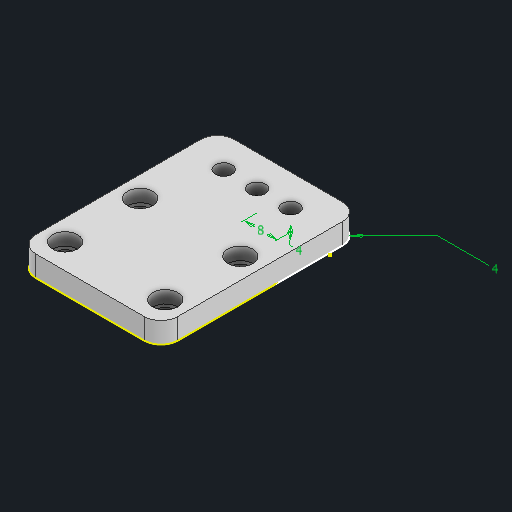
# Autodesk Inventor part: UR_rail_R_LinearWayCopler_v3
Saved by Autodesk Inventor 2026.2 (Build 302298000, 298)
## iProperties
Created: 2025-11-14
Part Number: UR_rail_R_LinearWayCopler_v3
Material: 일반
Document SubType Name: Modeling
Designer: work
Density: 1 g/cm^3
Appearance: 기본값
Author: work
Autodesk Inventor part; units mm, degrees
ref_plane "YZ Plane" through (0, 0, 0) normal (1, 0, 0) x (0, 1, 0)
ref_plane "XZ Plane" through (0, 0, 0) normal (0, 1, 0) x (-1, 0, 0)
ref_plane "XY Plane" through (0, 0, 0) normal (0, 0, 1) x (1, 0, 0)
sketch "스케치1" plane through (0, 0, 0) normal (0, 1, 0) x (-1, 0, 0)
  line L0 (-17, 15) -> (17, 15)
  line L1 (17, 15) -> (17, -15)
  line L2 (17, -15) -> (-17, -15)
  line L3 (-17, -15) -> (-17, 15)
  line L4 (-17, 15) -> (17, -15) construction
  line L5 (17, 15) -> (-17, -15) construction
  line L6 (12, 9) -> (-12, 9) construction
  line L7 (-12, 9) -> (-12, -9) construction
  line L8 (-12, -9) -> (12, -9) construction
  line L9 (12, -9) -> (12, 9) construction
  line L10 (12, 9) -> (-12, -9) construction
  line L11 (-12, 9) -> (12, -9) construction
  circle A0 centre (12, 9) radius 2
  circle A1 centre (12, -9) radius 2
  circle A2 centre (-12, 9) radius 2
  circle A3 centre (-12, -9) radius 2
  circle A4 centre (0, -25) radius 2
  circle A5 centre (0, -25) radius 7.5
  arc A6 (17, -15) -> (7.5, -25) centre (17.5132, -25) ccw
  arc A7 (-7.5, -25) -> (-17, -15) centre (-17.5132, -25) ccw
  line L12 (7.5, -25) -> (-7.5, -25) construction
  line L13 (0, -25) -> (0, 0) construction
  dimension "d0" = 34
  dimension "d1" = 30
  dimension "d2" = 24
  dimension "d3" = 18
  dimension "d4" = 4
  dimension "d5" = 4
  dimension "d6" = 4
  dimension "d7" = 4
  dimension "d8" = 4
  dimension "d9" = 15
  dimension "d10" = 25
  dimension "d11" = 15
  constraints: 28 end point, 8 centre point, 6 point on circle, 5 coincident, 4 midpoint, 4 parallel, 3 horizontal, 2 perpendicular, 2 tangent, 1 vertical
  measures "d0" distance of L1.end L2.end
  measures "d1" distance of L0.end L1.end
  measures "d2" distance of L8.end L7.end
  measures "d3" distance of L7.end L6.end
  measures "d4" diameter of A0
  measures "d5" diameter of A1
  measures "d6" diameter of A2
  measures "d7" diameter of A3
  measures "d8" diameter of A4
  measures "d9" diameter of A5
  measures "d10" distance of A4.centre L13.end
  measures "d11" distance of L12.start L12.end
extrude "돌출1" add sketch "스케치1" along normal blind 5
fillet "모깎기1" radius 4 4 edges at (-17, 2.5, 15) (17, 2.5, 15) (17, 2.5, -15) (-17, 2.5, -15)
sketch "스케치2" plane through (0, 5, 0) normal (0, 1, 0) x (1, 0, 0)
  arc A0 (-14.2883, 15.5204) -> (-17, 11.7335) centre (-13, 11.7335) ccw projected
  line L0 (-17, 11.7335) -> (-17, -11) projected
  arc A1 (-17, -11) -> (-13, -15) centre (-13, -11) ccw projected
  line L1 (-13, -15) -> (13, -15) projected
  arc A2 (13, -15) -> (17, -11) centre (13, -11) ccw projected
  line L2 (17, -11) -> (17, 11.7335) projected
  arc A3 (17, 11.7335) -> (14.2883, 15.5204) centre (13, 11.7335) ccw projected
  arc A4 (7.5, 25) -> (14.2883, 15.5204) centre (17.5132, 25) ccw projected
  arc A5 (7.5, 25) -> (-7.5, 25) centre (0, 25) ccw projected
  arc A6 (-14.2883, 15.5204) -> (-7.5, 25) centre (-17.5132, 25) ccw projected
  circle A7 centre (0, 25) radius 2 projected
  circle A8 centre (-12, -9) radius 2 projected
  circle A9 centre (-12, 9) radius 2 projected
  circle A10 centre (12, -9) radius 2 projected
  circle A11 centre (12, 9) radius 2 projected
  circle A12 centre (-12, -9) radius 3
  circle A13 centre (-12, 9) radius 3
  circle A14 centre (12, 9) radius 3
  circle A15 centre (12, -9) radius 3
  point P0 (0, 0)
  dimension "d15" = 6
  dimension "d16" = 6
  dimension "d17" = 6
  dimension "d18" = 6
  constraints: 4 centre point, 4 coincident
  measures "d15" diameter of A12
  measures "d16" diameter of A14
  measures "d17" diameter of A15
  measures "d18" diameter of A13
extrude "돌출2" cut sketch "스케치2" against normal blind 3 contours A8 | A9 | A10 | A11 | A12 | A13 | A14 | A15
sketch "스케치3" plane through (0, 0, 0) normal (0, -1, 0) x (1, 0, 0)
  circle A0 centre (12, 9) radius 3 projected
  circle A1 centre (-12, -9) radius 3 projected
  circle A2 centre (12, -9) radius 3 projected
  circle A3 centre (-12, 9) radius 3 projected
  arc A4 (-17, -11.7335) -> (-14.2883, -15.5204) centre (-13, -11.7335) ccw projected
  line L0 (-17, -11.7335) -> (-17, 11) projected
  arc A5 (-13, 15) -> (-17, 11) centre (-13, 11) ccw projected
  line L1 (-13, 15) -> (13, 15) projected
  arc A6 (17, 11) -> (13, 15) centre (13, 11) ccw projected
  line L2 (17, 11) -> (17, -11.7335) projected
  arc A7 (14.2883, -15.5204) -> (17, -11.7335) centre (13, -11.7335) ccw projected
  arc A8 (14.2883, -15.5204) -> (7.5, -25) centre (17.5132, -25) ccw projected
  arc A9 (-7.5, -25) -> (7.5, -25) centre (0, -25) ccw projected
  arc A10 (-7.5, -25) -> (-14.2883, -15.5204) centre (-17.5132, -25) ccw projected
  circle A11 centre (0, -25) radius 2 projected
  line L3 (0, -25) -> (8, -25) construction
  circle A12 centre (8, -25) radius 2
  line L4 (0, -32.5) -> (13, -32.5)
  arc A13 (-7.5, -25) -> (7.5, -25) centre (0, -25) ccw projected
  line L5 (17, -28.5) -> (17, -11.7335)
  arc A14 (13, -32.5) -> (17, -28.5) centre (13, -28.5) ccw
  line L6 (0, -32.5) -> (0, -25) construction
  circle A15 centre (-8, -25) radius 2
  line L7 (0, -32.5) -> (-13, -32.5)
  line L8 (-17, -28.5) -> (-17, -11.7335)
  arc A16 (-17, -28.5) -> (-13, -32.5) centre (-13, -28.5) ccw
  point P0 (0, 0)
  point P1 (-17.5132, -25)
  point P2 (7.6971, -23.0231)
  point P3 (7.2656, -26.8603)
  point P4 (-7.2656, -26.8603)
  point P5 (-7.6971, -23.0231)
  dimension "d21" = 8
  dimension "d22" = 4
  dimension "d23" = 4
  constraints: 12 end point, 5 point on circle, 5 symmetric about line, 4 centre point, 3 tangent, 2 horizontal, 1 coincident, 1 perpendicular, 1 vertical, 2 other
  measures "d21" distance of L3.start L3.end
  measures "d22" diameter of A12
  measures "d23" radius of A14
extrude "돌출3" add sketch "스케치3" against normal blind 5 contours A9 A12 A8 A7 L5 A14 L4
extrude "돌출4" cut sketch "스케치3" against normal through all contours A12 A8 A9 picked at (7.025, -24.6266)
extrude "돌출5" add sketch "스케치3" against normal blind 5 contours A4 A10 A15 A9 L7 A16 L8
extrude "돌출6" cut sketch "스케치3" against normal blind 5 contours A15 A9 A10 picked at (-7.0259, -24.6229)
